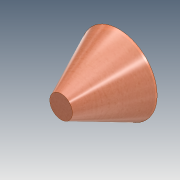
# Autodesk Inventor part: Materials Test Part._3
Saved by Autodesk Inventor 2020 (Build 240168000, 168)
## iProperties
Created: 2019-06-27
Part Number: Materials Test Part._3
Material: Walnut
Document SubType Name: Modeling
Designer: PC
Mass: 222.506 g
Surface Area: 309.679 cm^2
Volume: 365.964 cm^3
Density: 0.608 g/cm^3
Appearance: Walnut - Natural Polished
Author: PC
Autodesk Inventor part; units mm, degrees
ref_plane "YZ Plane" through (0, 0, 0) normal (1, 0, 0) x (0, 1, 0)
ref_plane "XZ Plane" through (0, 0, 0) normal (0, 1, 0) x (-1, 0, 0)
ref_plane "XY Plane" through (0, 0, 0) normal (0, 0, 1) x (1, 0, 0)
sketch "Sketch4" plane through (0, 0, 0) normal (0, 1, 0) x (-1, 0, 0)
  circle A0 centre (0, 0) radius 16.2788
  constraints: 1 centre point, 1 coincident
extrude "Extrusion1" add sketch "Sketch4" along normal blind 83.25 draft 25
body "Solid3"
